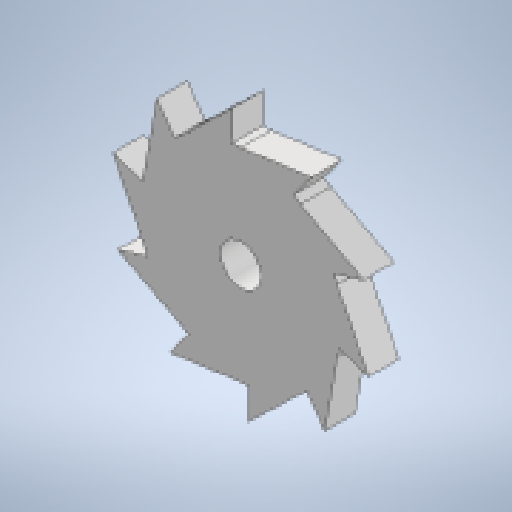
# Autodesk Inventor part: vibracion
Saved by Autodesk Inventor 2025.2 (Build 292293000, 293)
## iProperties
Created: 2025-05-17
Part Number: vibracion
Material: Generic
Document SubType Name: Modeling
Designer: laura
Density: 1 g/cm^3
Appearance: Default
Author: laura
Autodesk Inventor part; units mm, degrees
ref_plane "YZ Plane" through (0, 0, 0) normal (1, 0, 0) x (0, 1, 0)
ref_plane "XZ Plane" through (0, 0, 0) normal (0, 1, 0) x (-1, 0, 0)
ref_plane "XY Plane" through (0, 0, 0) normal (0, 0, 1) x (1, 0, 0)
sketch "Sketch1" plane through (0, 0, 0) normal (0, 0, 1) x (1, 0, 0)
  circle A0 centre (0, 0) radius 4
  circle A1 centre (0, 0) radius 21
  line L0 (10.4283, 18.2277) -> (14, 22.9676)
  line L1 (14, 22.9676) -> (0, 21)
  line L2 (0, 0) -> (0, 21) construction
  dimension "d8" = 42
  dimension "d9" = 8
  dimension "d11" = 45
  dimension "d20" = 82
  dimension "d21" = 14
  constraints: 6 end point, 2 centre point, 2 coincident, 2 point on circle, 1 vertical
  measures "d8" diameter of A1
  measures "d9" diameter of A0
  measures "d11" angle of L0 L1
  measures "d20" angle of L2 L1
  measures "d21" distance from line of L2 L0.end
extrude "Extrusion1" add sketch "Sketch1" along normal blind 6 contours A1
extrude "Extrusion2" add sketch "Sketch1" along normal blind 6 contours A1 L1 L0
pattern_circular "Circular Pattern1" count 12 over 360 about axis through (0, 0, 0) along (0, 0, 1) of "Extrusion2"
body "Solid1"
